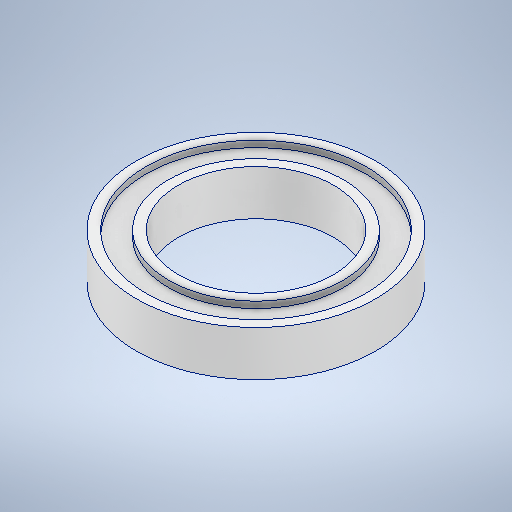
# Autodesk Inventor part: 轴承
Saved by Autodesk Inventor 2025 (Build 290162000, 162)
## iProperties
Created: 2026-11-07
Part Number: 轴承
Material: 铝 6061
Document SubType Name: Modeling
Designer: ylh00
Density: 2.7 g/cm^3
Appearance: 铝 - 平面
Mass: 9.96034 g
Surface Area: 29.7038 cm^2
Volume: 3.68902 cm^3
Author: ylh00
Autodesk Inventor part; units mm, degrees
ref_plane "YZ Plane" through (0, 0, 0) normal (1, 0, 0) x (0, 1, 0)
ref_plane "XZ Plane" through (0, 0, 0) normal (0, 1, 0) x (-1, 0, 0)
ref_plane "XY Plane" through (0, 0, 0) normal (0, 0, 1) x (1, 0, 0)
sketch "草图1" plane through (0, 0, 0) normal (0, 1, 0) x (-1, 0, 0)
  circle A0 centre (0, 0) radius 12
  circle A1 centre (0, 0) radius 18.5
  dimension "d0" = 24
  dimension "d1" = 37
  constraints: 2 centre point, 2 coincident
  measures "d0" diameter of A0
  measures "d1" diameter of A1
extrude "拉伸1" add sketch "草图1" along normal blind 7
sketch "草图2" plane through (0, 7, 0) normal (0, 1, 0) x (1, 0, 0)
  circle A0 centre (0, 0) radius 12 projected
  circle A1 centre (0, 0) radius 13.5
  circle A2 centre (0, 0) radius 17
  dimension "d4" = 27
  dimension "d5" = 34
  constraints: 2 centre point, 2 coincident
  measures "d4" diameter of A1
  measures "d5" diameter of A2
extrude "拉伸2" cut sketch "草图2" against normal blind 1 contours A2
sketch "草图3" plane through (0, 0, 0) normal (0, -1, 0) x (1, 0, 0)
  circle A0 centre (0, 0) radius 17
  circle A1 centre (0, 0) radius 13.5
  constraints: 2 centre point, 2 coincident
extrude "拉伸3" cut sketch "草图3" against normal blind 1
